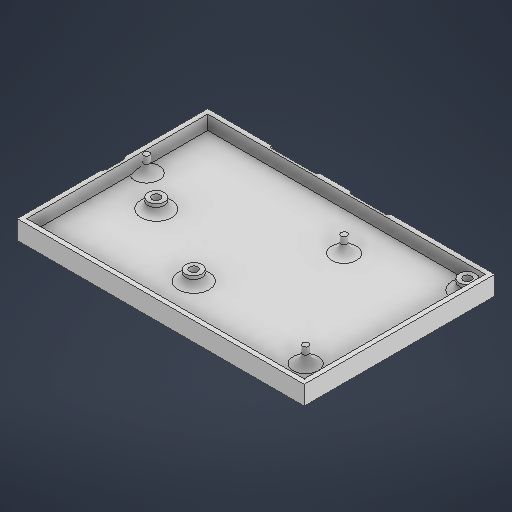
# Autodesk Inventor part: Inferior_plate
Saved by Autodesk Inventor 2027 (Build 310192000, 192)
## iProperties
Created: 2026-05-25
Part Number: Inferior_plate
Material: Genérico
Document SubType Name: Modeling
Designer: Luca Schiavi
Density: 1 g/cm^3
Appearance: Padrão
Author: Luca Schiavi
Autodesk Inventor part; units mm, degrees
ref_plane "YZ Plane" through (0, 0, 0) normal (1, 0, 0) x (0, 1, 0)
ref_plane "XZ Plane" through (0, 0, 0) normal (0, 1, 0) x (-1, 0, 0)
ref_plane "XY Plane" through (0, 0, 0) normal (0, 0, 1) x (1, 0, 0)
sketch "Esboço2" plane through (0, 0, 0) normal (0, 1, 0) x (-1, 0, 0)
  line L0 (60.8405, 40.396) -> (-60.8405, 40.396)
  line L1 (-60.8405, 40.396) -> (-60.8405, -40.396)
  line L2 (-60.8405, -40.396) -> (60.8405, -40.396)
  line L3 (60.8405, -40.396) -> (60.8405, 40.396)
  line L4 (-60.8405, -40.396) -> (60.8405, 40.396) construction
  line L5 (60.8405, -40.396) -> (-60.8405, 40.396) construction
  point P0 (0, 0)
  point P1 (0, 0)
  dimension "d0" = 121.681
  dimension "d1" = 80.792
  constraints: 12 end point, 2 midpoint, 2 parallel, 1 coincident, 1 horizontal, 1 perpendicular
  measures "d0" distance of L2.end L1.end
  measures "d1" distance of L0.end L1.end
extrude "Extrusão1" add sketch "Esboço2" along normal blind 8
sketch "Esboço3" plane through (0, 8, 0) normal (0, 1, 0) x (1, 0, 0)
  line L0 (-58.8405, 38.396) -> (58.8405, 38.396)
  line L1 (58.8405, 38.396) -> (58.8405, -38.396)
  line L2 (58.8405, -38.396) -> (-58.8405, -38.396)
  line L3 (-58.8405, -38.396) -> (-58.8405, 38.396)
  line L4 (0, 38.396) -> (0, -38.396) construction
  line L5 (58.8405, 0) -> (-58.8405, 0) construction
  line L6 (60.8405, -40.396) -> (60.8405, 40.396) construction
  line L7 (60.8405, 40.396) -> (-60.8405, 40.396) construction
  line L8 (60.8405, -40.396) -> (-60.8405, 40.396) construction
  line L9 (-60.8405, 40.396) -> (-60.8405, -40.396) construction
  line L10 (60.8405, 40.396) -> (-60.8405, -40.396) construction
  point P0 (0, 0)
  point P1 (0, 0)
  dimension "d4" = 76.792
  dimension "d5" = 117.681
  constraints: 16 end point, 8 midpoint, 2 parallel, 1 horizontal, 1 perpendicular
  measures "d4" distance of L0.end L1.end
  measures "d5" distance of L1.end L2.end
extrude "Extrusão2" cut sketch "Esboço3" against normal blind 6
sketch "Esboço4" plane through (0, 2, 0) normal (0, 1, 0) x (1, 0, 0)
  circle A0 centre (-56.1902, 9.8374) radius 1.3
  circle A1 centre (-40.9502, -1.3386) radius 1.75
  circle A2 centre (-6.5331, -19.8807) radius 1.75
  circle A3 centre (15.1839, 22.1564) radius 1.3
  circle A4 centre (54.808, 34.8564) radius 1.75
  circle A5 centre (47.569, -26.4847) radius 1.3
  circle A6 centre (-40.9502, -1.3386) radius 3.5
  circle A7 centre (54.808, 34.8564) radius 3.5
  circle A8 centre (-6.5331, -19.8807) radius 3.5
  line L0 (-58.8405, 38.396) -> (58.8405, 38.396) projected
  line L1 (-58.8405, -38.396) -> (-58.8405, 38.396) projected
  line L2 (58.8405, 38.396) -> (58.8405, -38.396) projected
  line L3 (58.8405, -38.396) -> (-58.8405, -38.396) projected
  line L4 (-58.5905, 38.146) -> (58.5905, 38.146) construction
  line L5 (58.5905, 38.146) -> (58.5905, -38.146) construction
  line L6 (58.5905, -38.146) -> (-58.5905, -38.146) construction
  line L7 (-58.5905, -38.146) -> (-58.5905, 38.146) construction
  point P0 (0, 0)
  dimension "d17" = 7
  dimension "d19" = 7
  dimension "d58" = 2.6
  dimension "d63" = 3.5
  dimension "d64" = 7
  dimension "d65" = 2.6
  dimension "d73" = 2.6
  dimension "d74" = 3.5
  dimension "d75" = 3.5
  dimension "d79" = 0.25
  dimension "d80" = 2.4003
  dimension "d81" = 28.3086
  dimension "d82" = 17.6403
  dimension "d83" = 36.8074
  dimension "d84" = 18.2653
  dimension "d85" = 52.0574
  dimension "d86" = 15.9896
  dimension "d87" = 43.4066
  dimension "d88" = 3.7825
  dimension "d89" = 3.2896
  dimension "d90" = 11.0215
  dimension "d91" = 11.6613
  constraints: 9 centre point, 8 end point, 3 coincident, 3 other
  measures "d17" diameter of A7
  measures "d19" diameter of A8
  measures "d58" diameter of A0
  measures "d63" diameter of A1
  measures "d64" diameter of A6
  measures "d65" diameter of A5
  measures "d73" diameter of A3
  measures "d74" diameter of A4
  measures "d75" diameter of A2
  measures "d79" distance between parallel lines of L1 L7
  measures "d80" distance from line of L7 A0.centre
  measures "d81" distance from line of L4 A0.centre
  measures "d82" distance from line of L7 A1.centre
  measures "d83" distance from line of L6 A1.centre
  measures "d84" distance from line of L6 A2.centre
  measures "d85" distance from line of L7 A2.centre
  measures "d86" distance from line of L4 A3.centre
  measures "d87" distance from line of L5 A3.centre
  measures "d88" distance from line of L5 A4.centre
  measures "d89" distance from line of L4 A4.centre
  measures "d90" distance from line of L5 A5.centre
  measures "d91" distance from line of L6 A5.centre
extrude "Extrusão5" add sketch "Esboço4" along normal blind 4.3 contours A6 | A7 | A8
extrude "Extrusão6" add sketch "Esboço4" along normal blind 7 contours A0 | A3 | A5
fillet "Arredondamento2" radius 3 3 edges at (-10.0331, 2, 19.8807) (-44.4502, 2, 1.3386) (51.308, 2, -34.8564)
fillet "Arredondamento3" radius 4 3 edges at (-57.4902, 2, -9.8374) (13.8839, 2, -22.1564) (46.269, 2, 26.4847)
sketch "Esboço7" plane through (-60.8405, 0, -40.396) normal (-1, 0, 0) x (0, 0, 1)
  line L0 (0, 0) -> (80.792, 0) construction
  line L1 (0, 0) -> (0, 8) construction
  line L2 (0, 8) -> (80.792, 8) construction
  line L3 (80.792, 0) -> (80.792, 8) construction
  line L4 (36.9906, 12.26) -> (43.4306, 12.26) construction
  arc A0 (45.6806, 10.01) -> (43.4306, 12.26) centre (43.4306, 10.01) ccw construction
  line L5 (45.6806, 10.01) -> (45.6806, 9.35) construction
  arc A1 (43.4306, 7.1) -> (45.6806, 9.35) centre (43.4306, 9.35) ccw
  line L6 (43.4306, 7.1) -> (36.9906, 7.1)
  arc A2 (34.7406, 9.35) -> (36.9906, 7.1) centre (36.9906, 9.35) ccw
  line L7 (34.7406, 9.35) -> (34.7406, 10.01) construction
  arc A3 (36.9906, 12.26) -> (34.7406, 10.01) centre (36.9906, 10.01) ccw construction
  line L8 (40.2106, 7.1) -> (40.2106, 12.26) construction
  line L9 (35.1906, 8) -> (45.2306, 8)
  line L10 (35.2406, 10.01) -> (35.2406, 9.35)
  arc A4 (35.2406, 9.35) -> (36.9906, 7.6) centre (36.9906, 9.35) ccw
  line L11 (36.9906, 7.6) -> (43.4306, 7.6)
  arc A5 (43.4306, 7.6) -> (45.1806, 9.35) centre (43.4306, 9.35) ccw
  line L12 (45.1806, 9.35) -> (45.1806, 10.01)
  arc A6 (45.1806, 10.01) -> (43.4306, 11.76) centre (43.4306, 10.01) ccw
  line L13 (43.4306, 11.76) -> (36.9906, 11.76)
  arc A7 (36.9906, 11.76) -> (35.2406, 10.01) centre (36.9906, 10.01) ccw
  point P0 (40.396, 0)
  dimension "d101" = 0.9
  dimension "d102" = 2.25
  dimension "d103" = 0.66
  dimension "d104" = 2.25
  dimension "d105" = 6.44
  dimension "d106" = 34.7406
  dimension "d135" = 0.5
  constraints: 20 end point, 18 point on circle, 8 centre point, 2 midpoint, 2 point on line, 10 other
  measures "d101" distance between parallel lines of L2 L6
  measures "d102" radius of A1
  measures "d103" distance of L5.start L5.end
  measures "d104" radius of A0
  measures "d105" distance of L6.start L6.end
  measures "d106" distance between parallel lines of L1 L7
  measures "d135" radial gap between concentric circles of A3 A7
revolve "Revolução2" cut sketch "Esboço7" angle 360 about axis through (-60.8405, 8, -5.2054) along (0, 0, 1) contours L6 A2 L9 A4 L11 A5 A1 | A5 L11 A4 L9
sketch "Esboço8" plane through (60.8405, 0, -40.396) normal (0, 0, -1) x (-1, 0, 0)
  line L0 (0, 0) -> (0, 8) construction
  line L1 (0, 8) -> (121.681, 8) construction
  line L2 (0, 0) -> (121.681, 0) construction
  line L3 (121.681, 0) -> (121.681, 8) construction
  line L4 (45.2895, 8) -> (59.7395, 8) construction
  line L5 (45.1395, 8.05) -> (45.1395, 9.9) construction
  arc A0 (45.2895, 10.05) -> (45.1395, 9.9) centre (45.2895, 9.9) ccw construction
  line L6 (52.5145, 10.05) -> (45.2895, 10.05) construction
  line L7 (56.8895, 10.05) -> (52.5145, 10.05) construction
  line L8 (56.8895, 10.05) -> (59.7395, 10.05) construction
  arc A1 (59.8895, 9.9) -> (59.7395, 10.05) centre (59.7395, 9.9) ccw construction
  line L9 (59.8895, 9.9) -> (59.8895, 8.05) construction
  line L10 (56.8895, 8) -> (59.7395, 8) construction
  line L11 (59.7395, 8.05) -> (59.7395, 8) construction
  line L12 (59.8895, 8.05) -> (59.7395, 8.05) construction
  line L13 (56.8895, 8) -> (52.5145, 8) construction
  line L14 (52.5145, 8) -> (45.2895, 8) construction
  line L15 (45.2895, 8) -> (45.2895, 8.05) construction
  line L16 (45.2895, 8.05) -> (45.1395, 8.05) construction
  line L17 (75.1566, 8.0103) -> (93.6267, 8.0103) construction
  line L18 (75.1566, 8.8312) -> (75.1566, 8.0103) construction
  line L19 (75.1566, 8.8312) -> (93.6267, 8.8312) construction
  line L20 (93.6267, 8.8312) -> (93.6267, 8.0103) construction
  line L21 (60.8895, 8.1495) -> (60.8895, 9.9)
  arc A2 (60.8895, 9.9) -> (59.7395, 11.05) centre (59.7395, 9.9) ccw
  line L22 (59.7395, 11.05) -> (56.8895, 11.05)
  line L23 (56.8895, 11.05) -> (52.5145, 11.05)
  line L24 (52.5145, 11.05) -> (45.2895, 11.05)
  arc A3 (45.2895, 11.05) -> (44.1395, 9.9) centre (45.2895, 9.9) ccw
  line L25 (44.1395, 9.9) -> (44.1395, 8.1495)
  line L26 (45.289, 7) -> (52.5145, 7)
  line L27 (52.5145, 7) -> (56.8895, 7)
  line L28 (56.8895, 7) -> (59.74, 7)
  line L29 (93.6267, 9.8312) -> (75.1566, 9.8312)
  line L30 (74.1566, 8.8312) -> (74.1566, 8.0103)
  line L31 (75.1566, 7.0103) -> (93.6267, 7.0103)
  line L32 (94.6267, 8.0103) -> (94.6267, 8.8312)
  arc A4 (59.74, 7) -> (60.8895, 8.1495) centre (59.74, 8.1495) ccw
  line L33 (52.5145, 11.05) -> (52.5145, 7) construction
  arc A5 (44.1395, 8.1495) -> (45.289, 7) centre (45.289, 8.1495) ccw
  arc A6 (74.1566, 8.0103) -> (75.1566, 7.0103) centre (75.1566, 8.0103) ccw
  arc A7 (75.1566, 9.8312) -> (74.1566, 8.8312) centre (75.1566, 8.8312) ccw
  arc A8 (94.6267, 8.8312) -> (93.6267, 9.8312) centre (93.6267, 8.8312) ccw
  arc A9 (93.6267, 7.0103) -> (94.6267, 8.0103) centre (93.6267, 8.0103) ccw
  line L34 (44.1493, 8) -> (60.8798, 8)
  line L35 (74.1566, 8) -> (94.6266, 8)
  point P0 (60.8405, 0)
  dimension "d108" = 1
  dimension "d109" = 1
  dimension "d110" = 1.15
  dimension "d112" = 14.45
  dimension "d113" = 1.15
  dimension "d117" = 1.1495
  dimension "d118" = 1.1495
  dimension "d119" = 1.7505
  dimension "d120" = 1.7505
  dimension "d121" = 44.1395
  dimension "d122" = 1
  dimension "d123" = 0.9897
  dimension "d124" = 1
  dimension "d125" = 0.8209
  dimension "d126" = 1
  dimension "d127" = 18.4701
  dimension "d128" = 0.8209
  dimension "d129" = 1
  dimension "d130" = 1
  dimension "d131" = 27.0543
  dimension "d132" = 16.7305
  dimension "d133" = 20.47
  constraints: 64 end point, 24 point on circle, 10 centre point, 10 tangent, 4 point on line, 3 equal radius, 3 symmetric about line, 1 perpendicular, 8 other
  measures "d108" distance between parallel lines of L9 L21
  measures "d109" distance between parallel lines of L19 L29
  measures "d110" radius of A3
  measures "d112" distance of L22.start L24.end
  measures "d113" radius of A2
  measures "d117" radius of A4
  measures "d118" radius of A5
  measures "d119" distance of L25.start L25.end
  measures "d120" distance of L21.start L21.end
  measures "d121" distance from line of L0.end L25
  measures "d122" distance between parallel lines of L26 L14
  measures "d123" distance between parallel lines of L31 L1
  measures "d124" radius of A6
  measures "d125" distance of L30.start L30.end
  measures "d126" radius of A7
  measures "d127" distance of L29.start L29.end
  measures "d128" distance of L32.start L32.end
  measures "d129" radius of A8
  measures "d130" radius of A9
  measures "d131" distance from line of L1.end L32
  measures "d132" distance of L34.start L34.end
  measures "d133" distance of L35.start L35.end
revolve "Revolução3" cut sketch "Esboço8" angle 360 about axis through (-14.3161, 8.0103, -40.396) along (-1, 0, 0) contours A4 L28 L27 L26 A5 L34 | A9 L31 A6 L35
